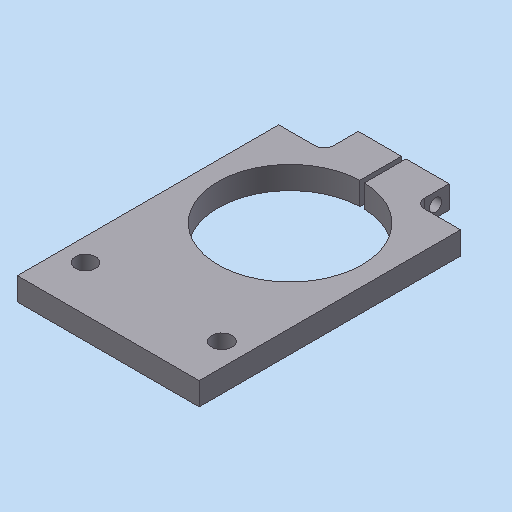
# Autodesk Inventor part: MM0867AN150_G01_147
Saved by Autodesk Inventor 2023.3 (Build 273359000, 359)
## iProperties
Created: 2018-11-09
Part Number: MM0867AN150_G01_147
Material: 3.3547 AlMg4,5Mn 0,7 -AW 5083
Document SubType Name: Modeling
Designer: fsm9bw
Density: 2.71 g/cm^3
Appearance: Metall-AL-6061 (gleichmäß.)
Mass: 173.858 g
Surface Area: 205.221 cm^2
Volume: 64.1542 cm^3
Description: =<RBPARTNOTITLE2>
RBMATERIAL: =<Material>
RBMATNO: =<Part Number>
RBPARTMADEOF: 10 x 130 x 80 (FM)
RBPARTNOTITLE1: manufactured part
RBPARTNOTITLE2: Anfertigungsteil
MaxAbmaße: 10 x 130 x 80 (FM)
AnP_Material_aktuell: =<Material>
AnP_Kommentar_aktuell: =<Comments>
AnP_Kategorie: 1
AnP_Material: =<Material>
RBDRAWINGMISSINGSPEC: --
RBSURFACE2: farbl. eloxiert
Author: fsm9bw
Comments: =<RBSURFACE2>
Keywords: =<RBPARTMADEOF>
Revision Number: 01
Autodesk Inventor part; units mm, degrees
ref_plane "YZ Plane" through (0, 0, 0) normal (1, 0, 0) x (0, 1, 0)
ref_plane "XZ Plane" through (0, 0, 0) normal (0, 1, 0) x (-1, 0, 0)
ref_plane "XY Plane" through (0, 0, 0) normal (0, 0, 1) x (1, 0, 0)
sketch "Skizze1" plane through (0, 0, 0) normal (0, 0, 1) x (1, 0, 0)
  line L0 (-40, 0) -> (40, 0)
  line L1 (40, 0) -> (40, 130)
  line L2 (40, 130) -> (-40, 130)
  line L3 (-40, 130) -> (-40, 0)
  line L4 (-56, 0) -> (56, 0) projected
  line L5 (0, -26) -> (0, 156) projected
  point P0 (0, 0)
  dimension "d0" = 80
  dimension "d1" = 130
  constraints: 8 end point, 2 parallel, 1 collinear, 1 horizontal, 1 perpendicular, 1 other
  measures "d0" distance of L0.start L0.end
  measures "d1" distance of L2.end L0.start
extrude "Extrusion1" add sketch "Skizze1" along normal blind 10
sketch "Skizze2" plane through (0, 0, 10) normal (0, 0, 1) x (1, 0, 0)
  line L0 (-40, 0) -> (40, 0) projected
  point P0 (0, 0)
  point P1 (-30, 20)
  point P2 (30, 20)
  dimension "d4" = 60
  dimension "d5" = 30
  dimension "d6" = 20
  constraints: 1 horizontal alignment
  measures "d4" distance of point (30, 20) point (-30, 20)
  measures "d5" horizontal distance of point (-30, 20) point (0, 0)
  measures "d6" distance from line of point (-30, 20) L0
hole "Bohrung1" at (-30, 20, 10) at (30, 20, 10) direction (0, 0, -1) diameter 9 end through all
sketch "Skizze3" plane through (0, 0, 10) normal (0, 0, 1) x (1, 0, 0)
  line L0 (-40, 0) -> (40, 0) projected
  line L1 (40, 130) -> (-40, 130) projected
  point P0 (0, 0)
  point P1 (0, 80)
  point P2 (0, 0)
  point P3 (0, 0)
  dimension "d14" = 50
  constraints: 2 midpoint, 2 vertical alignment
  measures "d14" distance from line of point (0, 80) L1
hole "Bohrung2" at (0, 80, 10) direction (0, 0, -1) diameter 63.4 end through all
sketch "Skizze4" plane through (0, 0, 10) normal (0, 0, 1) x (1, 0, 0)
  circle A0 centre (0, 80) radius 31.7 projected
  line L0 (40, 130) -> (-40, 130) projected
  line L1 (-1, 130) -> (1, 130)
  line L2 (1, 130) -> (1, 108.8642)
  line L3 (1, 108.8642) -> (-1, 108.8642)
  line L4 (-1, 108.8642) -> (-1, 130)
  point P0 (0, 0)
  dimension "d22" = 2
  dimension "d23" = 1
  constraints: 8 end point, 2 parallel, 1 horizontal, 1 perpendicular, 1 point on line
  measures "d22" distance between parallel lines of L2 L4
  measures "d23" distance from line of A0.centre L4
extrude "Extrusion2" cut sketch "Skizze4" against normal blind 10 contours L2 L3 L4 A0 | A0 L4 L0 L2 picked at (0.1111, 109.8089)
sketch "Skizze5" plane through (40, 0, 0) normal (1, 0, 0) x (0, 0, -1)
  line L0 (0, 0) -> (0, 130) projected
  line L1 (0, 130) -> (-10, 130) projected
  point P0 (-5, 124)
  dimension "d26" = 6
  dimension "d27" = 5
  measures "d26" distance from line of point (-5, 124) L1
  measures "d27" distance from line of point (-5, 124) L0
hole "Bohrung3" at (40, 124, 5) direction (-1, 0, 0) diameter 4.134 end through all counterbore diameter 5.5 counterbore depth 40 thread size "M5x0.8" designation "M5" class "6H" standard "ISO Metric profile"
sketch "Skizze6" plane through (0, 0, 10) normal (0, 0, 1) x (1, 0, 0)
  line L0 (-1, 130) -> (-40, 130) projected
  line L1 (-40, 130) -> (-40, 0) projected
  line L2 (40, 0) -> (40, 130) projected
  line L3 (40, 130) -> (1, 130) projected
  line L4 (-40, 115) -> (-24, 115)
  line L5 (-20, 119) -> (-20, 130)
  line L6 (-20, 130) -> (-40, 130)
  line L7 (-40, 130) -> (-40, 115)
  line L8 (40, 115) -> (24, 115)
  line L9 (20, 119) -> (20, 130)
  line L10 (20, 130) -> (40, 130)
  line L11 (40, 130) -> (40, 115)
  arc A0 (-24, 115) -> (-20, 119) centre (-24, 119) ccw
  arc A1 (20, 119) -> (24, 115) centre (24, 119) ccw
  point P0 (0, 0)
  point P1 (-20, 115)
  point P2 (20, 115)
  dimension "d35" = 20
  dimension "d36" = 20
  dimension "d37" = 15
  dimension "d38" = 15
  dimension "d39" = 4
  constraints: 16 end point, 8 point on line, 4 parallel, 4 point on circle, 4 tangent, 2 centre point, 2 horizontal, 2 perpendicular, 1 equal radius
  measures "d35" distance of L4.start point (-20, 115)
  measures "d36" distance of L8.start point (20, 115)
  measures "d37" distance between parallel lines of L6 L4
  measures "d38" distance of point (20, 115) L9.end
  measures "d39" radius of A0
extrude "Extrusion3" cut sketch "Skizze6" against normal blind 10
